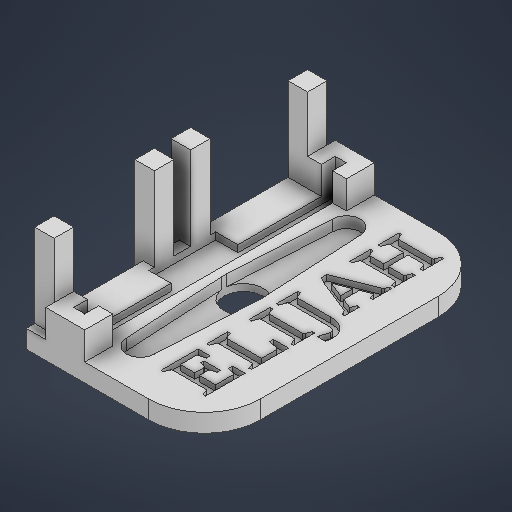
# Autodesk Inventor part: Ultrasonic Sensor Stand
Saved by Autodesk Inventor 2027 (Build 310192060, 192F)
## iProperties
Created: 2026-10-30
Part Number: Ultrasonic Sensor Stand
Material: Generic
Document SubType Name: Modeling
Designer: 6100673
Density: 1 g/cm^3
Appearance: Default
Author: 6100673
Autodesk Inventor part; units mm, degrees
ref_plane "YZ Plane" through (0, 0, 0) normal (1, 0, 0) x (0, 1, 0)
ref_plane "XZ Plane" through (0, 0, 0) normal (0, 1, 0) x (-1, 0, 0)
ref_plane "XY Plane" through (0, 0, 0) normal (0, 0, 1) x (1, 0, 0)
sketch "Sketch1" plane through (0, 0, 0) normal (0, 1, 0) x (-1, 0, 0)
  line L0 (0, 0) -> (0, -52)
  line L1 (0, -52) -> (-22, -52)
  line L2 (-32, -42) -> (-32, -10)
  line L3 (-22, 0) -> (0, 0)
  arc A0 (-22, 0) -> (-32, -10) centre (-22, -10) ccw
  arc A1 (-32, -42) -> (-22, -52) centre (-22, -42) ccw
  circle A2 centre (-13, -26) radius 3.5
  line L4 (0, -52) -> (-6, -52) construction
  line L5 (-6, -49.5) -> (-6, -32)
  line L6 (-6, -32) -> (-2, -32)
  line L7 (-2, -32) -> (-2, -20)
  line L8 (-2, -20) -> (-6, -20)
  line L9 (-6, -20) -> (-6, -2.5)
  line L10 (-6, -2.5) -> (-8, -2.5)
  line L11 (-8, -2.5) -> (-8, -49.5)
  line L12 (-8, -49.5) -> (-6, -49.5)
  point P0 (-32, -52)
  dimension "d0" = 52
  dimension "d1" = 32
  dimension "d2" = 10
  dimension "d3" = 10
  dimension "d6" = 7
  dimension "d7" = 6
  dimension "d8" = 2.5
  dimension "d9" = 17.5
  dimension "d10" = 4
  dimension "d11" = 12
  dimension "d12" = 17.5
  dimension "d13" = 2
  constraints: 26 end point, 9 perpendicular, 5 point on line, 4 point on circle, 4 tangent, 3 centre point, 1 vertical
  measures "d0" distance of L0.start L0.end
  measures "d1" distance of L0.end point (-32, -52)
  measures "d2" radius of A0
  measures "d3" radius of A1
  measures "d6" diameter of A2
  measures "d7" distance of L0.end L4.end
  measures "d8" distance of L4.end L5.start
  measures "d9" distance of L5.start L5.end
  measures "d10" distance of L5.end L6.end
  measures "d11" distance of L6.end L7.end
  measures "d12" distance of L8.end L9.end
  measures "d13" distance of L9.end L10.end
extrude "Extrusion1" add sketch "Sketch1" along normal blind 3.25
extrude "Extrusion2" add sketch "Sketch1" along normal blind 2 contours L12 L11 L10 L9 L8 L7 L6 L5
sketch "Sketch2" plane through (0, 3.25, 0) normal (0, 1, 0) x (1, 0, 0)
  circle A0 centre (13, 26) radius 3.5 construction
  line L0 (8, 49.5) -> (8, 2.5) construction
  circle A1 centre (13, 7.5) radius 2.5
  circle A2 centre (13, 44.5) radius 2.5
  line L1 (10.5, 7.5) -> (9.5, 26)
  line L2 (10.5, 44.5) -> (9.5, 26)
  line L3 (15.5, 7.5) -> (16.4948, 25.8101)
  line L4 (15.5, 44.5) -> (16.4948, 25.8101)
  point P0 (0, 0)
  dimension "d21" = 5
  dimension "d22" = 5
  constraints: 8 end point, 6 point on circle, 2 centre point, 1 tangent
  measures "d21" diameter of A1
  measures "d22" diameter of A2
extrude "Extrusion3" cut sketch "Sketch2" against normal blind 2
sketch "Sketch3" plane through (0, 3.25, 0) normal (0, 1, 0) x (1, 0, 0)
  line L0 (6, 32) -> (6, 49.5) projected
  line L1 (6, 49.5) -> (6, 47)
  line L2 (6, 47) -> (3.5, 47)
  line L3 (3.5, 47) -> (3.5, 52)
  line L4 (3.5, 52) -> (10.5, 52)
  line L5 (22, 52) -> (0, 52) projected
  line L6 (10.5, 52) -> (10.5, 47)
  line L7 (10.5, 47) -> (8, 47)
  line L8 (8, 47) -> (8, 49.5)
  line L9 (8, 49.5) -> (6, 49.5)
  line L10 (6, 2.5) -> (6, 20) projected
  line L11 (6, 2.5) -> (6, 5)
  line L12 (6, 5) -> (3.5, 5)
  line L13 (3.5, 5) -> (3.5, 0)
  line L14 (3.5, 0) -> (10.5, 0)
  line L15 (0, 0) -> (22, 0) projected
  line L16 (10.5, 0) -> (10.5, 5)
  line L17 (6, 5) -> (6, 2.5)
  line L18 (0, 52) -> (0, 0) construction
  line L19 (32, 10) -> (32, 42) construction
  line L20 (8, 2.5) -> (6, 2.5) projected
  line L21 (6, 2.5) -> (8, 2.5)
  line L22 (10.5, 5) -> (8.303, 5)
  line L23 (8.303, 5) -> (8, 5)
  dimension "d25" = 2.5
  dimension "d26" = 2.5
  dimension "d27" = 5
  dimension "d28" = 7
  dimension "d29" = 5
  dimension "d30" = 2.5
  dimension "d31" = 2.5
  dimension "d32" = 7
  dimension "d33" = 0.303
  constraints: 34 end point, 7 perpendicular, 6 point on line, 3 horizontal, 1 collinear
  measures "d25" distance of L0.end L1.end
  measures "d26" distance of L1.end L2.end
  measures "d27" distance of L2.end L3.end
  measures "d28" distance of L3.end L4.end
  measures "d29" distance of L4.end L6.end
  measures "d30" distance of L6.end L7.end
  measures "d31" distance of L10.start L11.end
  measures "d32" distance of L13.end L14.end
  measures "d33" distance of L22.end L23.end
extrude "Extrusion4" add sketch "Sketch3" along normal blind 5
sketch "Sketch4" plane through (0, 3.25, 0) normal (0, 1, 0) x (1, 0, 0)
  line L0 (8, 47) -> (8, 2.5) projected
  line L1 (8, 2.5) -> (8, 5)
  line L2 (8, 5) -> (10.5, 5)
  line L3 (10.5, 5) -> (10.5, 0)
  line L4 (10.5, 0) -> (3.5, 0)
  line L5 (3.5, 0) -> (3.5, 5)
  line L6 (3.5, 5) -> (6, 5)
  line L7 (6, 2.5) -> (6, 20) projected
  line L8 (8, 2.5) -> (6, 2.5) projected
  line L9 (6, 2.5) -> (8, 2.5)
  point P0 (0, 0)
  dimension "d36" = 2.5
  dimension "d37" = 2.5
  dimension "d38" = 90
  dimension "d39" = 7
  constraints: 14 end point, 4 perpendicular, 4 point on line, 1 collinear
  measures "d36" distance of L0.end L1.end
  measures "d37" distance of L1.end L2.end
  measures "d38" angle of L1 L2
  measures "d39" distance of L3.end L4.end
extrude "Extrusion5" add sketch "Sketch4" along normal blind 5
sketch "Sketch5" plane through (0, 3.25, 0) normal (0, 1, 0) x (1, 0, 0)
  line L0 (0, 0) -> (22, 0) construction
  line L1 (0, 0) -> (0, 1.5) construction
  line L2 (0, 1.5) -> (3.5, 1.5)
  line L3 (3.5, 0) -> (3.5, 5) projected
  line L4 (3.5, 1.5) -> (3.5, 5)
  line L5 (3.5, 5) -> (0, 5)
  line L6 (0, 52) -> (0, 0) projected
  line L7 (0, 1.5) -> (0, 5)
  line L8 (0, 5) -> (0, 21) construction
  line L9 (0, 21) -> (2, 21)
  line L10 (2, 21) -> (-1.5, 21)
  line L11 (-1.5, 21) -> (-1.5, 24.5)
  line L12 (-1.5, 24.5) -> (2, 24.5)
  line L13 (2, 20) -> (2, 32) projected
  line L14 (2, 24.5) -> (2, 26.5) construction
  line L15 (2, 26.5) -> (2, 27.5) construction
  line L16 (2, 27.5) -> (-1.5, 27.5)
  line L17 (-1.5, 27.5) -> (-1.5, 31)
  line L18 (-1.5, 31) -> (2, 31)
  line L19 (6, 47) -> (3.5, 47) projected
  line L20 (3.5, 47) -> (0, 47)
  line L21 (0, 47) -> (0, 50.5)
  line L22 (0, 50.5) -> (3.5, 50.5)
  line L23 (3.5, 47) -> (3.5, 52) projected
  line L24 (3.5, 50.5) -> (3.5, 47)
  dimension "d42" = 1.5
  dimension "d43" = 16
  dimension "d44" = 3.5
  dimension "d45" = 3.5
  dimension "d46" = 2
  dimension "d47" = 1
  dimension "d48" = 3.5
  dimension "d49" = 3.5
  constraints: 38 end point, 11 perpendicular, 10 point on line, 1 collinear, 1 horizontal, 1 vertical
  measures "d42" distance of L0.start L1.end
  measures "d43" distance of L5.end L8.end
  measures "d44" distance of L9.end L10.end
  measures "d45" distance of L10.end L11.end
  measures "d46" distance of L12.end L14.end
  measures "d47" distance of L14.end L15.end
  measures "d48" distance of L16.end L17.end
  measures "d49" distance of L20.end L21.end
extrude "Extrusion6" add sketch "Sketch5" along normal blind 15 and the other way blind 3.25 contours L6 L5 L3 L2 | L22 L23 L20 L6 | L18 L13 L16 L6 | L6 L16 L17 L18 | L12 L13 L9 L6 | L6 L10 L11 L12
sketch "Sketch6" plane through (0, 3.25, 0) normal (0, 1, 0) x (1, 0, 0)
  line L0 (18.6292, 5.009) -> (18.6292, 34.4679)
  line L1 (18.6292, 34.4679) -> (25.9556, 34.4679)
  line L2 (25.9556, 34.4679) -> (25.9556, 5.009)
  line L3 (25.9556, 5.009) -> (18.6292, 5.009)
  line L4 (26.6292, 5.5754) -> (26.169, 5.5754)
  line L5 (26.169, 5.5754) -> (25.8681, 6.4338)
  spline S0 degree 2 poles (25.8681, 6.4338) (25.8327, 6.5223) (25.7088, 6.6373) (25.5849, 6.6373) knots 0 0 0 1 2 2 2
  line L6 (25.5849, 6.6373) -> (19.6557, 6.6373)
  spline S1 degree 2 poles (19.6557, 6.6373) (19.5407, 6.6373) (19.4256, 6.5134) (19.3902, 6.4338) knots 0 0 0 1 2 2 2
  line L7 (19.3902, 6.4338) -> (19.0805, 5.5754)
  line L8 (19.0805, 5.5754) -> (18.6292, 5.5754)
  line L9 (18.6292, 5.5754) -> (18.6292, 12.2214)
  line L10 (18.6292, 12.2214) -> (20.7708, 12.2214)
  line L11 (20.7708, 12.2214) -> (20.7708, 11.5134)
  line L12 (20.7708, 11.5134) -> (19.6734, 11.2302)
  spline S2 degree 2 poles (19.6734, 11.2302) (19.5761, 11.2037) (19.4699, 11.0886) (19.4699, 10.9913) knots 0 0 0 1 2 2 2
  line L13 (19.4699, 10.9913) -> (19.4699, 8.2125)
  line L14 (19.4699, 8.2125) -> (22.0716, 8.2125)
  line L15 (22.0716, 8.2125) -> (22.0716, 9.8054)
  spline S3 degree 2 poles (22.0716, 9.8054) (22.0716, 9.9205) (21.9743, 10.009) (21.8681, 10.0444) knots 0 0 0 1 2 2 2
  line L16 (21.8681, 10.0444) -> (20.992, 10.3099)
  line L17 (20.992, 10.3099) -> (20.992, 10.8939)
  line L18 (20.992, 10.8939) -> (23.9566, 10.8939)
  line L19 (23.9566, 10.8939) -> (23.9566, 10.3099)
  line L20 (23.9566, 10.3099) -> (23.0893, 10.0444)
  spline S4 degree 2 poles (23.0893, 10.0444) (22.992, 10.0178) (22.8769, 9.9205) (22.8769, 9.8054) knots 0 0 0 1 2 2 2
  line L21 (22.8769, 9.8054) -> (22.8769, 8.2125)
  line L22 (22.8769, 8.2125) -> (25.7885, 8.2125)
  line L23 (25.7885, 8.2125) -> (25.7885, 11.4249)
  spline S5 degree 2 poles (25.7885, 11.4249) (25.7885, 11.5134) (25.6734, 11.6373) (25.5761, 11.655) knots 0 0 0 1 2 2 2
  line L24 (25.5761, 11.655) -> (24.3548, 11.9382)
  line L25 (24.3548, 11.9382) -> (24.3548, 12.6461)
  line L26 (24.3548, 12.6461) -> (26.6292, 12.6461)
  line L27 (26.6292, 12.6461) -> (26.6292, 5.5754)
  line L28 (26.6292, 13.8143) -> (26.169, 13.8143)
  line L29 (26.169, 13.8143) -> (25.8681, 14.6727)
  spline S6 degree 2 poles (25.8681, 14.6727) (25.8327, 14.7523) (25.7177, 14.8851) (25.5849, 14.8762) knots 0 0 0 1 2 2 2
  line L30 (25.5849, 14.8762) -> (19.6557, 14.8762)
  spline S7 degree 2 poles (19.6557, 14.8762) (19.5407, 14.8851) (19.4256, 14.7612) (19.3902, 14.6727) knots 0 0 0 1 2 2 2
  line L31 (19.3902, 14.6727) -> (19.0805, 13.8143)
  line L32 (19.0805, 13.8143) -> (18.6292, 13.8143)
  line L33 (18.6292, 13.8143) -> (18.6292, 17.54)
  line L34 (18.6292, 17.54) -> (19.0805, 17.54)
  line L35 (19.0805, 17.54) -> (19.3902, 16.6727)
  spline S8 degree 2 poles (19.3902, 16.6727) (19.4168, 16.593) (19.5407, 16.4515) (19.6557, 16.4515) knots 0 0 0 1 2 2 2
  line L36 (19.6557, 16.4515) -> (25.7885, 16.4515)
  line L37 (25.7885, 16.4515) -> (25.7885, 19.1948)
  spline S9 degree 2 poles (25.7885, 19.1948) (25.7885, 19.2922) (25.6557, 19.4249) (25.5495, 19.4426) knots 0 0 0 1 2 2 2
  line L38 (25.5495, 19.4426) -> (23.9123, 19.7523)
  line L39 (23.9123, 19.7523) -> (23.9123, 20.4692)
  line L40 (23.9123, 20.4692) -> (26.6292, 20.4692)
  line L41 (26.6292, 20.4692) -> (26.6292, 13.8143)
  line L42 (26.6292, 21.363) -> (26.169, 21.363)
  line L43 (26.169, 21.363) -> (25.8681, 22.2568)
  spline S10 degree 2 poles (25.8681, 22.2568) (25.8327, 22.363) (25.7088, 22.4692) (25.5849, 22.4692) knots 0 0 0 1 2 2 2
  line L44 (25.5849, 22.4692) -> (19.6557, 22.4692)
  spline S11 degree 2 poles (19.6557, 22.4692) (19.5407, 22.4692) (19.4256, 22.3453) (19.3902, 22.2568) knots 0 0 0 1 2 2 2
  line L45 (19.3902, 22.2568) -> (19.0805, 21.363)
  line L46 (19.0805, 21.363) -> (18.6292, 21.363)
  line L47 (18.6292, 21.363) -> (18.6292, 25.1594)
  line L48 (18.6292, 25.1594) -> (19.0805, 25.1594)
  line L49 (19.0805, 25.1594) -> (19.3902, 24.2656)
  spline S12 degree 2 poles (19.3902, 24.2656) (19.4256, 24.1771) (19.5407, 24.0444) (19.6557, 24.0444) knots 0 0 0 1 2 2 2
  line L50 (19.6557, 24.0444) -> (25.5849, 24.0444)
  spline S13 degree 2 poles (25.5849, 24.0444) (25.7088, 24.0444) (25.8327, 24.1771) (25.8681, 24.2656) knots 0 0 0 1 2 2 2
  line L51 (25.8681, 24.2656) -> (26.169, 25.1594)
  line L52 (26.169, 25.1594) -> (26.6292, 25.1594)
  line L53 (26.6292, 25.1594) -> (26.6292, 21.363)
  spline S14 degree 2 poles (19.6557, 27.4957) (19.5407, 27.4957) (19.4256, 27.3807) (19.3902, 27.2833) knots 0 0 0 1 2 2 2
  line L54 (19.3902, 27.2833) -> (19.0805, 26.2922)
  line L55 (19.0805, 26.2922) -> (18.6292, 26.2922)
  line L56 (18.6292, 26.2922) -> (18.6292, 30.1506)
  line L57 (18.6292, 30.1506) -> (19.0805, 30.1506)
  line L58 (19.0805, 30.1506) -> (19.3902, 29.301)
  spline S15 degree 2 poles (19.3902, 29.301) (19.4256, 29.2037) (19.5407, 29.0886) (19.6557, 29.0886) knots 0 0 0 1 2 2 2
  line L59 (19.6557, 29.0886) -> (25.5318, 29.0886)
  spline S16 degree 2 poles (25.5318, 29.0886) (26.6557, 29.0886) (28.2132, 28.2922) (29.0362, 26.9382) (29.0362, 26.0886) knots 0 0 0 1 2 3 3 3
  spline S17 degree 2 poles (29.0362, 26.0886) (29.0362, 25.9382) (28.9831, 25.4692) (28.8946, 24.9824) (28.8592, 24.8143) knots 0 0 0 1 2 3 3 3
  line L60 (28.8592, 24.8143) -> (27.4699, 24.8674)
  line L61 (27.4699, 24.8674) -> (27.4699, 25.2125)
  spline S18 degree 2 poles (27.4699, 25.2125) (27.5495, 25.3984) (27.7619, 25.9647) (27.93, 26.54) (27.93, 26.7435) knots 0 0 0 1 2 3 3 3
  spline S19 degree 2 poles (27.93, 26.7435) (27.93, 26.9824) (27.7973, 27.2568) (27.6646, 27.3276) knots 0 0 0 1 2 2 2
  spline S20 degree 2 poles (27.6646, 27.3276) (27.4876, 27.4249) (26.3194, 27.4957) (25.4787, 27.4957) knots 0 0 0 1 2 2 2
  line L62 (25.4787, 27.4957) -> (19.6557, 27.4957)
  line L63 (26.6292, 30.5311) -> (26.1778, 30.5311)
  line L64 (26.1778, 30.5311) -> (25.93, 31.1063)
  spline S21 degree 2 poles (25.93, 31.1063) (25.8327, 31.301) (25.6203, 31.3895) knots 0 0 0 1 1 1
  line L65 (25.6203, 31.3895) -> (19.9389, 33.6638)
  line L66 (19.9389, 33.6638) -> (18.6292, 34.3364)
  line L67 (18.6292, 34.3364) -> (18.6292, 35.3718)
  line L68 (18.6292, 35.3718) -> (25.638, 38.1329)
  spline S22 degree 2 poles (25.638, 38.1329) (25.7354, 38.1771) (25.9123, 38.3187) (25.9389, 38.4072) knots 0 0 0 1 2 2 2
  line L69 (25.9389, 38.4072) -> (26.1778, 38.9913)
  line L70 (26.1778, 38.9913) -> (26.6292, 38.9913)
  line L71 (26.6292, 38.9913) -> (26.6292, 35.6373)
  line L72 (26.6292, 35.6373) -> (26.1778, 35.6373)
  line L73 (26.1778, 35.6373) -> (25.8504, 36.5754)
  line L74 (25.8504, 36.5754) -> (21.1247, 34.6904)
  line L75 (21.1247, 34.6904) -> (20.3814, 34.4692)
  line L76 (20.3814, 34.4692) -> (20.3814, 34.3718)
  line L77 (20.3814, 34.3718) -> (25.8238, 32.2656)
  line L78 (25.8238, 32.2656) -> (26.1778, 33.2214)
  line L79 (26.1778, 33.2214) -> (26.6292, 33.2214)
  line L80 (26.6292, 33.2214) -> (26.6292, 30.5311)
  line L81 (24.0097, 32.8851) -> (23.1601, 33.2037)
  line L82 (23.1601, 33.2037) -> (23.1601, 35.5931)
  line L83 (23.1601, 35.5931) -> (24.0097, 35.9205)
  line L84 (24.0097, 35.9205) -> (24.0097, 32.8851)
  line L85 (26.6292, 39.4869) -> (26.169, 39.4869)
  line L86 (26.169, 39.4869) -> (25.8681, 40.3453)
  spline S23 degree 2 poles (25.8681, 40.3453) (25.8327, 40.4338) (25.7088, 40.5488) (25.5849, 40.5488) knots 0 0 0 1 2 2 2
  line L87 (25.5849, 40.5488) -> (19.6557, 40.5488)
  spline S24 degree 2 poles (19.6557, 40.5488) (19.5407, 40.5488) (19.4256, 40.4249) (19.3902, 40.3453) knots 0 0 0 1 2 2 2
  line L88 (19.3902, 40.3453) -> (19.0805, 39.4869)
  line L89 (19.0805, 39.4869) -> (18.6292, 39.4869)
  line L90 (18.6292, 39.4869) -> (18.6292, 43.2037)
  line L91 (18.6292, 43.2037) -> (19.0805, 43.2037)
  line L92 (19.0805, 43.2037) -> (19.3991, 42.3541)
  spline S25 degree 2 poles (19.3991, 42.3541) (19.4256, 42.2568) (19.5495, 42.124) (19.6557, 42.124) knots 0 0 0 1 2 2 2
  line L93 (19.6557, 42.124) -> (22.0716, 42.124)
  line L94 (22.0716, 42.124) -> (22.0716, 45.6727)
  line L95 (22.0716, 45.6727) -> (19.6557, 45.6727)
  spline S26 degree 2 poles (19.6557, 45.6727) (19.5407, 45.6727) (19.4256, 45.5488) (19.3991, 45.4515) knots 0 0 0 1 2 2 2
  line L96 (19.3991, 45.4515) -> (19.0805, 44.6019)
  line L97 (19.0805, 44.6019) -> (18.6292, 44.6019)
  line L98 (18.6292, 44.6019) -> (18.6292, 48.3276)
  line L99 (18.6292, 48.3276) -> (19.0805, 48.3276)
  line L100 (19.0805, 48.3276) -> (19.3902, 47.478)
  spline S27 degree 2 poles (19.3902, 47.478) (19.4256, 47.3807) (19.5407, 47.2568) (19.6557, 47.2568) knots 0 0 0 1 2 2 2
  line L101 (19.6557, 47.2568) -> (25.5849, 47.2568)
  spline S28 degree 2 poles (25.5849, 47.2568) (25.7088, 47.2568) (25.8327, 47.3895) (25.8681, 47.478) knots 0 0 0 1 2 2 2
  line L102 (25.8681, 47.478) -> (26.169, 48.3276)
  line L103 (26.169, 48.3276) -> (26.6292, 48.3276)
  line L104 (26.6292, 48.3276) -> (26.6292, 44.6019)
  line L105 (26.6292, 44.6019) -> (26.169, 44.6019)
  line L106 (26.169, 44.6019) -> (25.8681, 45.4515)
  spline S29 degree 2 poles (25.8681, 45.4515) (25.8238, 45.5488) (25.7088, 45.6727) (25.5849, 45.6727) knots 0 0 0 1 2 2 2
  line L107 (25.5849, 45.6727) -> (22.8769, 45.6727)
  line L108 (22.8769, 45.6727) -> (22.8769, 42.124)
  line L109 (22.8769, 42.124) -> (25.5849, 42.124)
  spline S30 degree 2 poles (25.5849, 42.124) (25.7088, 42.124) (25.8327, 42.2479) (25.8681, 42.3541) knots 0 0 0 1 2 2 2
  line L110 (25.8681, 42.3541) -> (26.169, 43.2037)
  line L111 (26.169, 43.2037) -> (26.6292, 43.2037)
  line L112 (26.6292, 43.2037) -> (26.6292, 39.4869)
  point P0 (0, 0)
  dimension "d0" = 52
  dimension "d1" = 32
  dimension "d2" = 10
  dimension "d3" = 10
  dimension "d7" = 6
  dimension "d8" = 2.5
  dimension "d9" = 17.5
  dimension "d10" = 4
  dimension "d11" = 12
  dimension "d12" = 17.5
  dimension "d13" = 2
  constraints: 2 other
emboss "Emboss1" sketch "Sketch6" operation cut depth 1 direction (0, -1, 0) contours L0 L10 L11 L12 S2 L13 L14 L15 S3 L16 L17 L18 L19 L20 S4 L21 L22 L23 S5 L24 L25 L26 L2 L5 S0 L6 S1 L7 L8 | L2 L26 L27 L4 L5 | L0 L34 L35 S8 L36 L37 S9 L38 L39 L40 L2 L29 S6 L30 S7 L31 L32 | L2 L40 L41 L28 L29 | L0 L48 L49 S12 L50 S13 L51 L2 L43 S10 L44 S11 L45 L46 | L2 L51 L52 L53 L42 L43 | L0 L57 L58 S15 L59 S16 L2 S20 L62 S14 L54 L55 | L2 S16 S17 L60 L61 S18 S19 S20 | L0 L1 L76 L77 L82 L81 L84 L78 L2 L64 S21 L65 L66 | L67 L68 S22 L69 L70 L71 L72 L73 L74 L84 L83 L82 L75 L1 | L2 L78 L79 L80 L63 L64 | L82 L74 L84 L1 | L1 L84 L77 L82 | L77 L84 L81 L82 | L82 L83 L84 L74 | L85 L86 S23 L87 S24 L88 L89 L90 L91 L92 S25 L93 L94 L95 S26 L96 L97 L98 L99 L100 S27 L101 S28 L102 L103 L104 L105 L106 S29 L107 L108 L109 S30 L110 L111 L112
body "Solid1"
